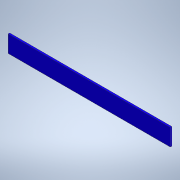
# Autodesk Inventor part: laterala_dreapta
Saved by Autodesk Inventor 2022.6 (Build 266554000, 554)
## iProperties
Created: 2025-04-03
Part Number: laterala_dreapta
Material: Generic
Document SubType Name: Modeling
Designer: Dragos Macovei
Density: 1 g/cm^3
Appearance: Default
Author: Dragos Macovei
Autodesk Inventor part; units mm, degrees
ref_plane "YZ Plane" through (0, 0, 0) normal (1, 0, 0) x (0, 1, 0)
ref_plane "XZ Plane" through (0, 0, 0) normal (0, 1, 0) x (-1, 0, 0)
ref_plane "XY Plane" through (0, 0, 0) normal (0, 0, 1) x (1, 0, 0)
sketch "Sketch1" plane through (0, 0, 0) normal (0, 0, 1) x (1, 0, 0)
  line L0 (0, 0) -> (1910, 0)
  line L1 (1910, 0) -> (1910, 200)
  line L2 (1910, 200) -> (0, 200)
  line L3 (0, 200) -> (0, 0)
  point P0 (0, 100)
  dimension "d8" = 200
  dimension "d9" = 1910
  constraints: 8 end point, 2 parallel, 1 horizontal, 1 midpoint, 1 perpendicular
  measures "d8" distance between parallel lines of L0 L2
  measures "d9" distance from line of L1 point (0, 100)
extrude "PAL" add sketch "Sketch1" along normal blind 18
body "Solid1"
